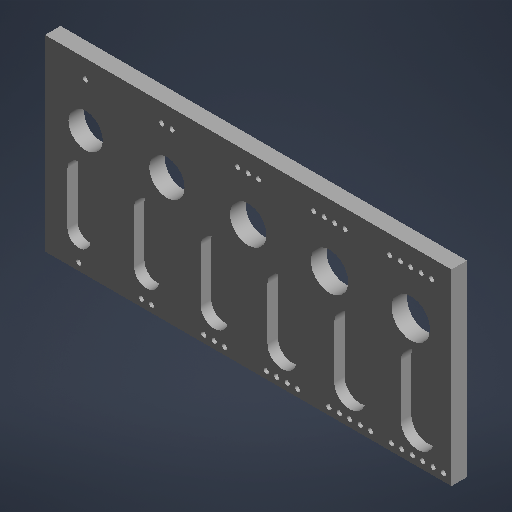
# Autodesk Inventor part: Prueba_horn
Saved by Autodesk Inventor 2027 (Build 310192060, 192F)
## iProperties
Part Number: Prueba_horn
Material: Genérico
Document SubType Name: Modelado
Designer: rodri
Appearance: Por defecto
Author: rodri
Autodesk Inventor part; units mm, degrees
ref_plane "Plano YZ" through (0, 0, 0) normal (1, 0, 0) x (0, 1, 0)
ref_plane "Plano XZ" through (0, 0, 0) normal (0, 1, 0) x (-1, 0, 0)
ref_plane "Plano de trabajo1" through (0, 0, 3) normal (0, 0, 1) x (1, 0, 0)
sketch "Boceto1" plane through (0, 0, 0) normal (0, 0, 1) x (1, 0, 0)
  line L0 (0, 0) -> (78, 0)
  line L1 (78, 0) -> (78, 36)
  line L2 (78, 36) -> (0, 36)
  line L3 (0, 36) -> (0, 0)
  constraints: 8 end point, 2 parallel, 1 horizontal, 1 perpendicular
extrude "Extrusión1" add sketch "Boceto1" along normal blind 3
sketch "Boceto2" plane through (0, 0, 0) normal (0, 0, 1) x (1, 0, 0)
  circle A0 centre (7.8, 24) radius 3.3
  circle A1 centre (23.4, 24) radius 3.4
  circle A2 centre (39, 24) radius 3.5
  circle A3 centre (54.6, 24) radius 3.6
  circle A4 centre (70.2, 24) radius 3.7
  constraints: 5 centre point
extrude "Extrusión2" cut sketch "Boceto2" along normal blind 4
sketch "Boceto3" plane through (0, 0, 3) normal (0, 0, 1) x (1, 0, 0)
  circle A0 centre (7.8, 32.5) radius 0.5
  circle A1 centre (22.4, 32.5) radius 0.5
  circle A2 centre (24.4, 32.5) radius 0.5
  circle A3 centre (37, 32.5) radius 0.5
  circle A4 centre (39, 32.5) radius 0.5
  circle A5 centre (41, 32.5) radius 0.5
  circle A6 centre (51.6, 32.5) radius 0.5
  circle A7 centre (53.6, 32.5) radius 0.5
  circle A8 centre (55.6, 32.5) radius 0.5
  circle A9 centre (57.6, 32.5) radius 0.5
  circle A10 centre (66.2, 32.5) radius 0.5
  circle A11 centre (68.2, 32.5) radius 0.5
  circle A12 centre (70.2, 32.5) radius 0.5
  circle A13 centre (72.2, 32.5) radius 0.5
  circle A14 centre (74.2, 32.5) radius 0.5
  constraints: 15 centre point
extrude "Extrusión3" cut sketch "Boceto3" against normal blind 0.6
sketch "Boceto4" plane through (0, 0, 3) normal (0, 0, 1) x (1, 0, 0)
  line L0 (4.3, 6) -> (8.7, 6)
  line L1 (8.7, 6) -> (8.7, 16)
  line L2 (8.7, 16) -> (4.3, 16)
  line L3 (4.3, 16) -> (4.3, 6)
  circle A0 centre (6.5, 6) radius 2.2
  circle A1 centre (6.5, 16) radius 2.2
  line L4 (17.1, 6) -> (21.9, 6)
  line L5 (21.9, 6) -> (21.9, 16)
  line L6 (21.9, 16) -> (17.1, 16)
  line L7 (17.1, 16) -> (17.1, 6)
  circle A2 centre (19.5, 6) radius 2.4
  circle A3 centre (19.5, 16) radius 2.4
  line L8 (29.9, 6) -> (35.1, 6)
  line L9 (35.1, 6) -> (35.1, 16)
  line L10 (35.1, 16) -> (29.9, 16)
  line L11 (29.9, 16) -> (29.9, 6)
  circle A4 centre (32.5, 6) radius 2.6
  circle A5 centre (32.5, 16) radius 2.6
  line L12 (42.7, 6) -> (48.3, 6)
  line L13 (48.3, 6) -> (48.3, 16)
  line L14 (48.3, 16) -> (42.7, 16)
  line L15 (42.7, 16) -> (42.7, 6)
  circle A6 centre (45.5, 6) radius 2.8
  circle A7 centre (45.5, 16) radius 2.8
  line L16 (55.5, 6) -> (61.5, 6)
  line L17 (61.5, 6) -> (61.5, 16)
  line L18 (61.5, 16) -> (55.5, 16)
  line L19 (55.5, 16) -> (55.5, 6)
  circle A8 centre (58.5, 6) radius 3
  circle A9 centre (58.5, 16) radius 3
  line L20 (68.3, 6) -> (74.7, 6)
  line L21 (74.7, 6) -> (74.7, 16)
  line L22 (74.7, 16) -> (68.3, 16)
  line L23 (68.3, 16) -> (68.3, 6)
  circle A10 centre (71.5, 6) radius 3.2
  circle A11 centre (71.5, 16) radius 3.2
  constraints: 48 end point, 12 centre point, 12 parallel, 6 horizontal, 6 perpendicular
extrude "Extrusión4" cut sketch "Boceto4" against normal blind 2
sketch "Boceto5" plane through (0, 0, 3) normal (0, 0, 1) x (1, 0, 0)
  circle A0 centre (6.5, 1.4) radius 0.5
  circle A1 centre (18.5, 1.4) radius 0.5
  circle A2 centre (20.5, 1.4) radius 0.5
  circle A3 centre (30.5, 1.4) radius 0.5
  circle A4 centre (32.5, 1.4) radius 0.5
  circle A5 centre (34.5, 1.4) radius 0.5
  circle A6 centre (42.5, 1.4) radius 0.5
  circle A7 centre (44.5, 1.4) radius 0.5
  circle A8 centre (46.5, 1.4) radius 0.5
  circle A9 centre (48.5, 1.4) radius 0.5
  circle A10 centre (54.5, 1.4) radius 0.5
  circle A11 centre (56.5, 1.4) radius 0.5
  circle A12 centre (58.5, 1.4) radius 0.5
  circle A13 centre (60.5, 1.4) radius 0.5
  circle A14 centre (62.5, 1.4) radius 0.5
  circle A15 centre (66.5, 1.4) radius 0.5
  circle A16 centre (68.5, 1.4) radius 0.5
  circle A17 centre (70.5, 1.4) radius 0.5
  circle A18 centre (72.5, 1.4) radius 0.5
  circle A19 centre (74.5, 1.4) radius 0.5
  circle A20 centre (76.5, 1.4) radius 0.5
  constraints: 21 centre point
extrude "Extrusión5" cut sketch "Boceto5" against normal blind 0.6
